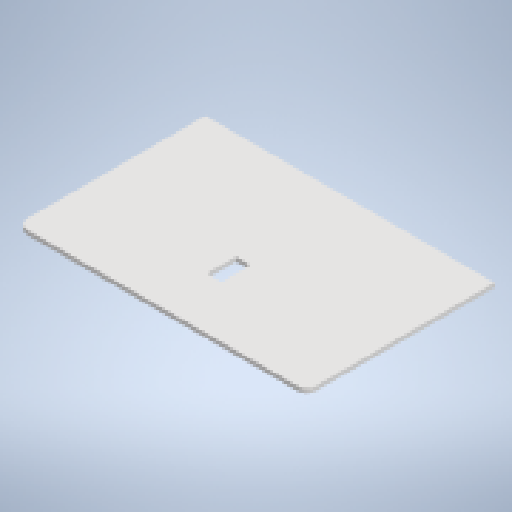
# Autodesk Inventor part: topo
Saved by Autodesk Inventor 2025.2 (Build 292293000, 293)
## iProperties
Created: 2026-05-27
Part Number: topo
Material: Generic
Document SubType Name: Modeling
Designer: joaoc
Density: 1 g/cm^3
Appearance: Default
Author: joaoc
Autodesk Inventor part; units mm, degrees
ref_plane "YZ Plane" through (0, 0, 0) normal (1, 0, 0) x (0, 1, 0)
ref_plane "XZ Plane" through (0, 0, 0) normal (0, 1, 0) x (-1, 0, 0)
ref_plane "XY Plane" through (0, 0, 0) normal (0, 0, 1) x (1, 0, 0)
sketch "Sketch1" plane through (0, 0, 0) normal (0, 1, 0) x (-1, 0, 0)
  arc A0 (-373.6, 13.2) -> (-386.8, 0) centre (-373.6, 0) ccw
  line L0 (-373.6, 13.2) -> (0, 13.2)
  arc A1 (13.2, 0) -> (0, 13.2) centre (0, 0) ccw
  line L1 (13.2, 0) -> (13.2, -246.8)
  line L2 (-386.8, -246.8) -> (-386.8, 0)
  line L3 (-196.8, -59.1) -> (-176.8, -59.1)
  line L4 (-176.8, -59.1) -> (-176.8, -99.1)
  line L5 (-176.8, -99.1) -> (-196.8, -99.1)
  line L6 (-196.8, -99.1) -> (-196.8, -59.1)
  line L7 (-386.8, -246.8) -> (13.2, -246.8)
  point P0 (-386.8, 0)
  constraints: 16 end point, 4 point on circle, 2 centre point
extrude "Extrusion1" add sketch "Sketch1" along normal blind 6
body "Solid1"
